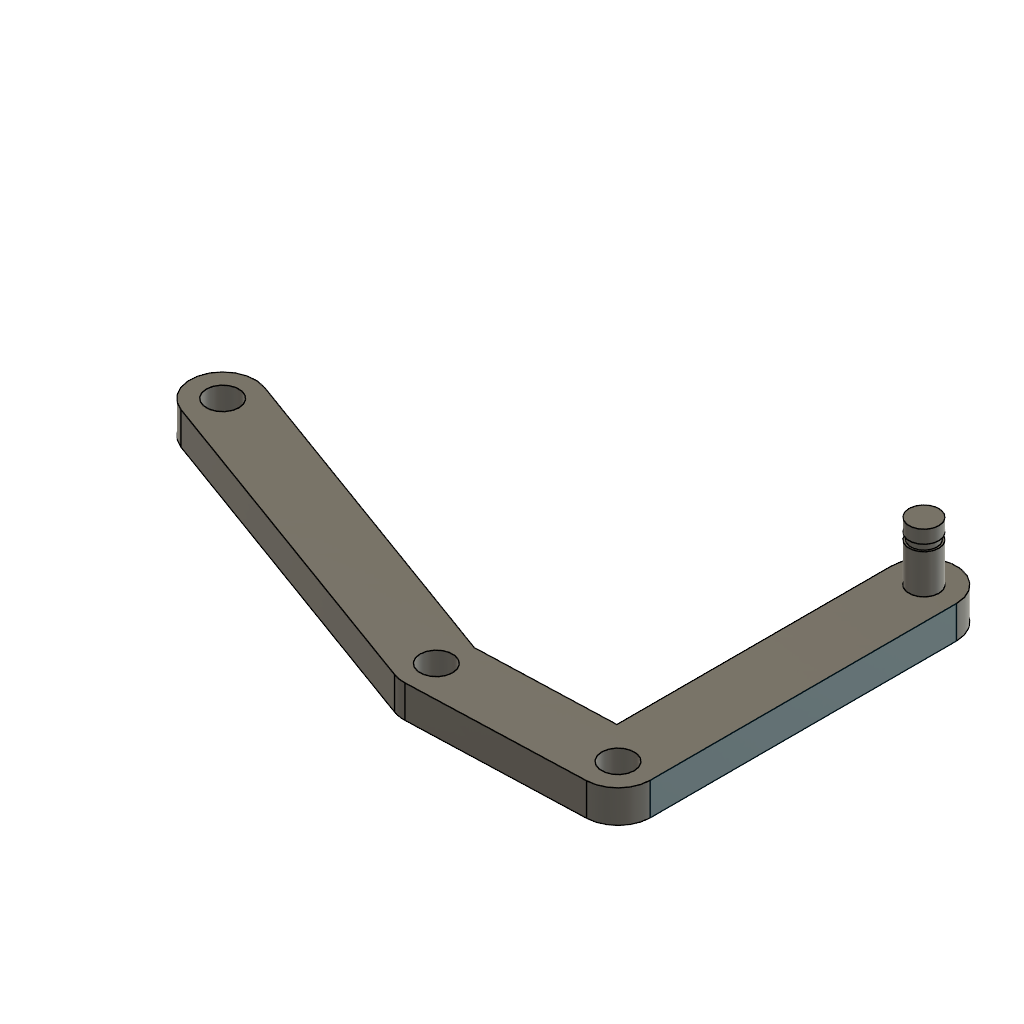
link 3 (Autodesk Fusion 360 design; units mm, degrees)
part number: 2026-11-18-20-16-10-797
Autodesk Fusion 360 part; units mm, degrees
sketch "Sketch1" plane through (0, 0, 0) normal (0, 1, 0) x (1, 0, 0)
  line L0 (0, 0) -> (26.9841, 0.9255)
  line L1 (26.9841, 0.9255) -> (26.9841, 47.9255)
  line L2 (26.9841, 47.9255) -> (0, 0)
  line L3 (0, 0) -> (-51.6714, 18.8432)
  circle A0 centre (26.9841, 47.9255) radius 2.5
  circle A1 centre (26.9841, 0.9255) radius 2.5
  circle A2 centre (0, 0) radius 2.5
  circle A3 centre (-51.6714, 18.8432) radius 2.5
  circle A4 centre (26.9841, 47.9255) radius 5
  circle A5 centre (26.9841, 0.9255) radius 5
  circle A6 centre (0, 0) radius 5
  circle A7 centre (-51.6714, 18.8432) radius 5
  line L4 (-1.713, -4.6974) -> (-53.3844, 14.1458)
  line L5 (0.8025, 5.0295) -> (-49.9584, 23.5406)
  line L6 (27.1555, -4.0715) -> (0.1555, -4.9976)
  line L7 (26.9841, 5.9255) -> (0.8025, 5.0295)
  line L8 (31.9837, 0.8627) -> (31.9841, 47.9255)
  line L9 (21.9841, 0.9255) -> (21.9841, 47.9255)
  dimension "d1" = 55
  dimension "d2" = 27
  dimension "d3" = 47
  dimension "d5" = 158
  dimension "d6" = 55
  dimension "d7" = 5
  dimension "d8" = 5
  dimension "d9" = 5
  dimension "d10" = 5
  dimension "d11" = 10
  dimension "d12" = 10
  dimension "d13" = 10
  dimension "d14" = 10
  dimension "d15" = 55
  dimension "d17" = 27
  dimension "d19" = 0.004
  dimension "d20" = 0
  dimension "d22" = 10
  constraint coincident L0.start L2.end
  constraint vertical L1
  constraint coincident L1.end L2.start
  constraint coincident L0.end L1.start
  constraint coincident L3.end A3.centre
  constraint concentric A0 A4
  constraint concentric A1 A5
  constraint concentric A2 A6
  constraint concentric A3 A7
  constraint parallel L3 L4
  constraint coincident A6 L4.start
  constraint tangent A6 L4
  constraint tangent A6 L5
  constraint parallel L0 L6
  constraint coincident A5 L6.start
  constraint tangent A5 L6
  constraint coincident A5 L7.start
  constraint coincident L1 L7.start
  constraint coincident A5 L8.start
  constraint coincident A4 L8.end
  constraint tangent A4 L8
  constraint coincident A5 L9.start
  constraint coincident A4 L9.end
  constraint tangent A4 L9
  constraint vertical L9
  measures "d1" distance of L0.start L1.end
  measures "d2" distance of L0.start L0.end
  measures "d3" distance of L0.end L1.end
  measures "d5" angle of L0 L3
  measures "d6" distance of L0.start L3.end
  measures "d7" diameter of A0
  measures "d8" diameter of A1
  measures "d9" diameter of A2
  measures "d10" diameter of A3
  measures "d11" diameter of A4
  measures "d12" diameter of A5
  measures "d13" diameter of A6
  measures "d14" diameter of A7
  measures "d15" distance of L4.start L4.end
  measures "d17" horizontal distance of L6.start L6.end
  measures "d19" angle of L6 L7
  measures "d20" angle of L1 L8
  measures "d22" distance of L4 L5
extrude "Extrude1" add sketch "Sketch1" along normal blind 5 contours L0 L2 A2 A6 | L0 L3 A2 A6 | L2 L3 A2 A6 | L0 L2 A5 A6 L7 L9 | L0 A5 A6 L6 | L2 L3 A6 A7 L5 L7 | L3 A6 A7 L4 | L0 L1 A1 A5 L7 | L0 L1 A1 A5 L8 | A7 | A5 L7 L9 | L2 A4 L9 | L1 L2 A4 A5 L7 L9 | A5 L7 | L1 L2 A0 A4 | L1 L2 A0 A4 | L1 A4 A5 L8 makes body 1
sketch "Sketch3" plane through (0, 0, 0) normal (0, -1, 0) x (1, 0, 0)
  circle A0 centre (0, 0) radius 2.5
  circle A1 centre (26.9841, -0.9255) radius 2.5
  circle A2 centre (-51.6714, -18.8432) radius 2.5
  circle A3 centre (26.9841, -47.9255) radius 2.5
  line L0 (31.9841, -47.9255) -> (31.9837, -0.8627)
  arc A4 (31.9837, -0.8627) -> (27.1555, 4.0715) centre (26.9841, -0.9255) ccw
  line L1 (27.1555, 4.0715) -> (0.1714, 4.9971)
  arc A5 (0.1714, 4.9971) -> (-1.713, 4.6974) centre (0, 0) ccw
  line L2 (-1.713, 4.6974) -> (-53.3844, -14.1458)
  arc A6 (-53.3844, -14.1458) -> (-49.9584, -23.5406) centre (-51.6714, -18.8432) ccw
  line L3 (-49.9584, -23.5406) -> (0.8025, -5.0295)
  line L4 (0.8025, -5.0295) -> (21.9841, -5.7544)
  line L5 (21.9841, -5.7544) -> (21.9841, -47.9255)
  arc A7 (21.9841, -47.9255) -> (31.9841, -47.9255) centre (26.9841, -47.9255) ccw
  circle A8 centre (26.9841, -47.9255) radius 2.5
  constraint concentric A3 A8
extrude "Extrude2" add sketch "Sketch3" against normal blind 8 contours A3 A8 bodies 1
sketch "Sketch4" plane through (0, 8, 0) normal (0, 1, 0) x (-1, 0, 0)
  circle A0 centre (-26.9841, -47.9255) radius 2.5
  circle A1 centre (-26.9841, -47.9255) radius 2.45
  dimension "d28" = 4.9
  constraint concentric A0 A1
  measures "d28" diameter of A1
extrude "Extrude3" add sketch "Sketch4" along normal blind 1 contours A1 bodies 1
sketch "Sketch5" plane through (0, 9, 0) normal (0, 1, 0) x (-1, 0, 0)
  circle A0 centre (-26.9841, -47.9255) radius 2.45
  circle A1 centre (-26.9841, -47.9255) radius 2.5
  dimension "d31" = 5
  constraint concentric A0 A1
  measures "d31" diameter of A1
extrude "Extrude4" add sketch "Sketch5" along normal blind 2 separate body makes body 2
extrude "Extrude5" add 1 faces at (28.3656, 9, -48.4385) along direction (0, 1, 0) blind 2 on bodies 1 bodies 1 2
sketch "Sketch6" plane through (0, 11, 0) normal (0, 1, 0) x (-1, 0, 0)
  circle A0 centre (-26.9841, -47.9255) radius 2.5
sketch "Sketch7" plane through (0, 11, 0) normal (0, 1, 0) x (-1, 0, 0)
  circle A0 centre (-27, -48) radius 2.45
  dimension "d36" = 4.9
  measures "d36" diameter of A0
extrude "Extrude6" cut sketch "Sketch7" against normal blind 6 bodies 1
extrude "Extrude7" cut sketch "Sketch6" against normal blind 6 bodies 1
sketch "Sketch8" plane through (0, 5, 0) normal (0, 1, 0) x (-1, 0, 0)
  circle A0 centre (0, 0) radius 2.5
  circle A1 centre (-26.9841, -0.9255) radius 2.5
  circle A2 centre (51.6714, -18.8432) radius 2.5
  line L0 (-31.9837, -0.8627) -> (-31.9841, -47.9255)
  arc A3 (-31.9841, -47.9255) -> (-21.9841, -47.9255) centre (-26.9841, -47.9255) ccw
  line L1 (-21.9841, -47.9255) -> (-21.9841, -5.7544)
  line L2 (-21.9841, -5.7544) -> (-0.8025, -5.0295)
  line L3 (-0.8025, -5.0295) -> (49.9584, -23.5406)
  arc A4 (49.9584, -23.5406) -> (53.3844, -14.1458) centre (51.6714, -18.8432) ccw
  line L4 (53.3844, -14.1458) -> (1.713, 4.6974)
  arc A5 (1.713, 4.6974) -> (-0.1714, 4.9971) centre (0, 0) ccw
  line L5 (-0.1714, 4.9971) -> (-27.1555, 4.0715)
  arc A6 (-27.1555, 4.0715) -> (-31.9837, -0.8627) centre (-26.9841, -0.9255) ccw
  circle A7 centre (-26.9841, -47.9255) radius 2.45
  dimension "d41" = 4.9
  constraint concentric A3 A7
  measures "d41" diameter of A7
extrude "Extrude8" add sketch "Sketch8" along normal blind 7 contours A7 bodies 1
sketch "Sketch9" plane through (0, 12, 0) normal (0, 1, 0) x (-1, 0, 0)
  circle A0 centre (-26.9841, -47.9255) radius 2.45
extrude "Extrude9" cut sketch "Sketch9" against normal blind 1 bodies 1
sketch "Sketch10" plane through (0, 11, 0) normal (0, 1, 0) x (-1, 0, 0)
  circle A0 centre (-26.9841, -47.9255) radius 2.45
  circle A1 centre (-26.9841, -47.9255) radius 2.3
  dimension "d46" = 4.6
  constraint concentric A0 A1
  measures "d46" diameter of A1
extrude "Extrude10" cut sketch "Sketch10" against normal blind 6 bodies 1
sketch "Sketch11" plane through (0, 11, 0) normal (0, 1, 0) x (-1, 0, 0)
  circle A0 centre (-26.9841, -47.9255) radius 2.3
  circle A1 centre (-26.9841, -47.9255) radius 2
  dimension "d49" = 4
  constraint concentric A0 A1
  measures "d49" diameter of A1
extrude "Extrude11" add sketch "Sketch11" along normal blind 1 contours A1 bodies 1
sketch "Sketch12" plane through (0, 12, 0) normal (0, 1, 0) x (-1, 0, 0)
  circle A0 centre (-26.9841, -47.9255) radius 2
  circle A1 centre (-26.9841, -47.9255) radius 2.3
  dimension "d52" = 4.6
  constraint concentric A0 A1
  measures "d52" diameter of A1
extrude "Extrude12" add sketch "Sketch12" along normal blind 2 contours A0 | A1 bodies 1
sketch "Sketch13" plane through (31.9837, 0, 0.0003) normal (1, 0, 0.000008) x (0.000008, 0, -1)
  line L0 (0.863, 0) -> (47.9258, 0)
  line L1 (47.9258, 0) -> (47.9258, 5)
  line L2 (47.9258, 5) -> (0.863, 5)
  line L3 (0.863, 5) -> (0.863, 0)
